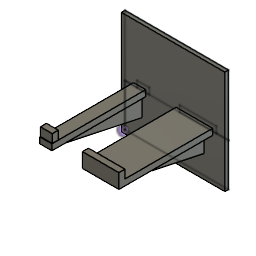
H_suporte_valvula_gas (Autodesk Fusion 360 design; units mm, degrees)
Autodesk Fusion 360 part; units mm, degrees
sketch "Esboço1" plane through (0, 0, 0) normal (0, 0, 1) x (1, 0, 0)
  line L0 (0, 0) -> (85, 0)
  line L1 (85, 0) -> (85, 85)
  line L2 (85, 85) -> (0, 85)
  line L3 (0, 85) -> (0, 0)
  line L4 (0, 0) -> (0, 35)
  line L5 (0, 35) -> (85, 35)
  line L6 (85, 35) -> (75, 35)
  line L7 (75, 35) -> (45, 35)
  line L8 (45, 35) -> (45, 40)
  line L9 (45, 40) -> (75, 40)
  line L10 (75, 40) -> (75, 35)
  line L11 (0, 35) -> (10, 35)
  line L12 (10, 35) -> (20, 35)
  line L13 (20, 35) -> (20, 40)
  line L14 (20, 40) -> (10, 40)
  line L15 (10, 40) -> (10, 35)
  dimension "d1" = 85
  dimension "d2" = 85
  dimension "d3" = 35
  dimension "d4" = 10
  dimension "d5" = 30
  dimension "d6" = 5
  dimension "d7" = 10
  dimension "d8" = 10
  dimension "d9" = 5
  constraint horizontal L0
  constraint vertical L1
  constraint horizontal L2
  constraint vertical L3
  constraint coincident L0.start L3.end
  constraint coincident L3 L4.end
  constraint coincident L1 L5.end
  constraint perpendicular L1 L5
  constraint perpendicular L1 L6
  constraint horizontal L7
  constraint vertical L8
  constraint horizontal L9
  constraint vertical L10
  constraint perpendicular L4 L11
  constraint horizontal L12
  constraint vertical L13
  constraint horizontal L14
  constraint vertical L15
  measures "d1" distance of L0.start L0.end
  measures "d2" distance of L0.start L2.end
  measures "d3" distance of L0.start L4.end
  measures "d4" distance of L5.end L6.end
  measures "d5" distance of L6.end L7.end
  measures "d6" distance of L6.end L9.end
  measures "d7" distance of L4.end L11.end
  measures "d8" distance of L11.end L12.end
  measures "d9" distance of L11.end L14.end
extrude "Extrusão1" add sketch "Esboço1" along normal blind 3
extrude "Extrusão2" add sketch "Esboço1" along normal blind 80 contours L5 L12 L13 L14 L15 | L5 L7 L8 L9 L10
sketch "Esboço2" plane through (0, 40, 0) normal (0, 1, 0) x (-1, 0, 0)
  line L0 (-75, 3) -> (-45, 3)
  line L1 (-45, 3) -> (-45, 80)
  line L2 (-45, 80) -> (-75, 80)
  line L3 (-75, 80) -> (-75, 3)
  line L4 (-45, 80) -> (-75, 80)
  line L5 (-75, 80) -> (-75, 75)
  line L6 (-75, 75) -> (-45, 75)
  line L7 (-45, 75) -> (-45, 80)
  line L8 (-19.9551, 79.62) -> (-10.156, 79.62)
  line L9 (-10.156, 79.62) -> (-10.156, 74.62)
  line L10 (-10.156, 74.62) -> (-19.9551, 74.62)
  line L11 (-19.9551, 74.62) -> (-19.9551, 79.62)
  dimension "d14" = 5
  dimension "d15" = 5
  constraint horizontal L4
  constraint vertical L5
  constraint horizontal L6
  constraint vertical L7
  constraint coincident L1.end L2.start
  constraint horizontal L8
  constraint vertical L9
  constraint horizontal L10
  constraint vertical L11
  measures "d14" distance of L1.end L6.end
  measures "d15" distance of L8.start L10.end
extrude "Extrusão3" add sketch "Esboço2" along normal blind 7 contours L1 L2 L3 L4 L5 L6 L7 | L8 L9 L10 L11
ref_plane "Plano de trabalho1" through (60, 41, 41.5) normal (1, 0, 0) x (0, 1, 0)
sketch "Esboço3" plane through (60, 0, 0) normal (1, 0, 0) x (0, 0, -1)
  line L0 (0, 0) -> (0, 18)
  line L1 (0, 18) -> (0, 34.888)
  line L2 (0, 18) -> (0, 34.888)
  line L3 (0, 18) -> (0, 35)
  line L4 (0, 35) -> (-80, 35)
  line L5 (-80, 35) -> (0, 18)
  dimension "d19" = 18
  dimension "d29" = 17
  dimension "d30" = 80
  constraint coincident L0.start origin
  constraint vertical L0
  constraint perpendicular L3 L4
  measures "d19" distance of L0.start L0.end
  measures "d29" distance of L0.end L3.end
  measures "d30" distance of L3.end L4.end
extrude "Extrusão4" add sketch "Esboço3" along normal mid plane 16
ref_plane "Plano de trabalho2" through (15, 37.5, 41.5) normal (1, 0, 0) x (0, 1, 0)
sketch "Esboço4" plane through (15, 0, 0) normal (1, 0, 0) x (0, 0, -1)
  line L0 (0, 0) -> (0, 18)
  line L1 (0, 18) -> (0, 35)
  line L2 (0, 35) -> (-80, 35)
  line L3 (0, 18) -> (-80, 35)
  dimension "d24" = 18
  dimension "d25" = 17
  dimension "d26" = 80
  constraint coincident L0.start origin
  constraint vertical L0
  constraint parallel L0 L1
  constraint perpendicular L1 L2
  measures "d24" distance of L0.start L0.end
  measures "d25" distance of L0.end L1.end
  measures "d26" distance of L1.end L2.end
extrude "Extrusão5" add sketch "Esboço4" along normal mid plane 4
